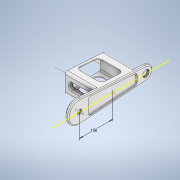
# Autodesk Inventor part: 1.3_1_SideArm
Saved by Autodesk Inventor 2021 (Build 250183000, 183)
## iProperties
Created: 2025-11-12
Part Number: 1.3_1_SideArm
Material: ABS Plastic
Document SubType Name: Modeling
Designer: Admin
Density: 1.06 g/cm^3
Appearance: Smooth - White
Mass: 683.15 g
Surface Area: 1228.56 cm^2
Volume: 644.481 cm^3
Author: Admin
Autodesk Inventor part; units mm, degrees
ref_plane "YZ Plane" through (0, 0, 0) normal (1, 0, 0) x (0, 1, 0)
ref_plane "XZ Plane" through (0, 0, 0) normal (0, 1, 0) x (-1, 0, 0)
ref_plane "XY Plane" through (0, 0, 0) normal (0, 0, 1) x (1, 0, 0)
sketch "Sketch1" plane through (0, 0, 0) normal (1, 0, 0) x (0, 1, 0)
  circle A0 centre (0, 0) radius 50
  circle A1 centre (0, -300) radius 30
  line L0 (0, 0) -> (0, -300) construction
  line L1 (49.8888, -3.3333) -> (29.9333, -302)
  line L2 (-49.8888, -3.3333) -> (-29.9333, -302)
  dimension "d0" = 300
  dimension "d1" = 100
  dimension "d2" = 60
  constraints: 6 end point, 4 point on circle, 3 tangent, 2 centre point, 1 coincident, 1 equal length, 1 vertical
  measures "d0" distance of L0.start L0.end
  measures "d1" diameter of A0
  measures "d2" diameter of A1
extrude "Extrusion1" add sketch "Sketch1" along normal blind 11
sketch "Sketch2" plane through (0, 0, 0) normal (0, 1, 0) x (-1, 0, 0)
  line L0 (0, 0) -> (0, 42.5)
  line L1 (0, 50) -> (0, -3.3333) projected
  line L2 (0, 42.5) -> (1, 42.5)
  line L3 (1, 42.5) -> (1, 40)
  line L4 (1, 40) -> (10, 40)
  line L5 (10, 40) -> (10, 0)
  line L6 (10, 0) -> (0, 0)
  dimension "d7" = 40
  dimension "d8" = 10
  dimension "d9" = 1
  dimension "d99" = 42.5
  constraints: 12 end point, 5 perpendicular, 1 collinear
  measures "d7" distance of L4.end L5.end
  measures "d8" distance between parallel lines of L0 L5
  measures "d9" distance of L0.end L2.end
  measures "d99" distance between parallel lines of L2 L6
revolve "Revolution1" add sketch "Sketch2" angle 360 about axis through (-10, 0, 0) along (1, 0, 0)
sketch "Sketch3" plane through (0, 0, 0) normal (0, 1, 0) x (-1, 0, 0)
  line L0 (10, -40) -> (10, 40) projected
  line L1 (10, -30) -> (-2, -30)
  line L2 (-2, -30) -> (-2, -12)
  line L3 (-2, -12) -> (-5, -12)
  line L4 (-5, -12) -> (-5, -10)
  line L5 (-5, -10) -> (-11, -10)
  line L6 (-11, -10) -> (-11, 0)
  line L7 (-11, 50) -> (-11, -3.3333) projected
  line L8 (-11, 0) -> (10, 0)
  line L9 (10, 0) -> (10, -30)
  line L10 (14.2, 0) -> (-15.2, 0) projected
  point P0 (0, 0)
  point P1 (10, 0)
  dimension "d11" = 30
  dimension "d12" = 12
  dimension "d13" = 6
  dimension "d14" = 3
  dimension "d15" = 12
  dimension "d16" = 10
  constraints: 16 end point, 6 perpendicular, 2 point on line, 1 collinear, 1 horizontal
  measures "d11" distance between parallel lines of L8 L1
  measures "d12" distance of L1.start L1.end
  measures "d13" distance of L4.end L5.end
  measures "d14" distance of L2.end L3.end
  measures "d15" distance between parallel lines of L8 L3
  measures "d16" distance between parallel lines of L8 L5
revolve "Revolution2" cut sketch "Sketch3" angle 360 about axis through (-10, 0, 0) along (1, 0, 0)
sketch "Sketch4" plane through (2, 0, 0) normal (-1, 0, 0) x (0, 0, 1)
  line L0 (-16.2635, -16.2635) -> (16.2635, -16.2635)
  line L1 (16.2635, -16.2635) -> (16.2635, 16.2635)
  line L2 (16.2635, 16.2635) -> (-16.2635, 16.2635)
  line L3 (-16.2635, 16.2635) -> (-16.2635, -16.2635)
  line L4 (-16.2635, -16.2635) -> (16.2635, 16.2635) construction
  line L5 (16.2635, -16.2635) -> (-16.2635, 16.2635) construction
  circle A0 centre (0, 0) radius 23
  dimension "d18" = 46
  constraints: 12 end point, 3 coincident, 2 midpoint, 2 parallel, 2 perpendicular, 1 horizontal, 3 other
hole "Hole1" at (2, 16.2635, 16.2635) at (2, -16.2635, -16.2635) direction (1, 0, 0) diameter 4.5 end through all clearance for "Countersunk Flat Head Screw ISO 2009/7046" size "M4" standard "ISO"
sketch "Sketch5" plane through (0, 0, 0) normal (0, 1, 0) x (-1, 0, 0)
  line L0 (0, -300) -> (-11, -300)
  line L1 (0, -300) -> (-11, -300)
  line L2 (-11, -300) -> (-11, -314)
  line L3 (-11, -314) -> (-7, -314)
  line L4 (-7, -314) -> (-7, -315)
  line L5 (-7, -315) -> (0, -315)
  line L6 (0, -315) -> (0, -300)
  line L7 (-40, 0) -> (163, 0) projected
  line L8 (0, -406) -> (0, 126) projected
  line L9 (-11, -3.3333) -> (-11, -302) projected
  point P0 (0, 0)
  dimension "d26" = 15
  dimension "d27" = 1
  dimension "d28" = 7
  dimension "d100" = 300
  constraints: 14 end point, 5 perpendicular, 3 collinear
  measures "d26" distance between parallel lines of L0 L5
  measures "d27" distance between parallel lines of L5 L3
  measures "d28" distance of L4.end L5.end
  measures "d100" distance between parallel lines of L7 L0
revolve "Revolution3" cut sketch "Sketch5" angle 360 about axis through (0, 0, -300) along (1, 0, 0)
sketch "Sketch7" plane through (11, 0, 0) normal (1, 0, 0) x (0, 0, -1)
  line L0 (406, 0) -> (-126, 0) projected
  point P0 (0, 0)
  point P1 (150, 0)
  dimension "d36" = 150
  constraints: 1 point on line
  measures "d36" distance of point (0, 0) point (150, 0)
sketch "Sketch8" plane through (0, 0, 0) normal (-1, 0, 0) x (0, 0, 1)
  line L0 (0, 70) -> (0, -70) projected
  circle A0 centre (-300, 0) radius 14 projected
  line L1 (-302, 29.9333) -> (-3.3333, 49.8888) projected
  line L2 (-406, 0) -> (126, 0) projected
  line L3 (-302, 29.9333) -> (-3.3333, 49.8888) projected
  line L4 (-80, 44.7663) -> (-80, -44.7663)
  line L5 (-3.3333, -49.8888) -> (-302, -29.9333) projected
  line L6 (-260, 32.7395) -> (-260, -32.7395)
  line L7 (-240, 34.0758) -> (-240, -34.0758)
  line L8 (-100, 43.43) -> (-100, -43.43)
  line L9 (-260, -32.7395) -> (-240, -34.0758)
  line L10 (-260, 32.7395) -> (-240, 34.0758)
  line L11 (-100, 43.43) -> (-80, 44.7663)
  line L12 (-100, -43.43) -> (-80, -44.7663)
  point P0 (0, 0)
  point P1 (-240, 34.0758)
  point P2 (-260, 32.7395)
  point P3 (-100, 43.43)
  dimension "d66" = 40
  dimension "d67" = 80
  dimension "d68" = 20
  dimension "d69" = 20
  constraints: 16 end point, 7 point on line, 4 collinear, 3 vertical, 1 coincident, 1 parallel
  measures "d66" distance from line of point (-300, 0) L6
  measures "d67" distance between parallel lines of L0 L4
  measures "d68" distance between parallel lines of L7 L6
  measures "d69" distance between parallel lines of L4 L8
extrude "Extrusion4" add sketch "Sketch8" along normal blind 134 contours L1 L7 L2 L6 | L2 L7 L5 L6 | L1 L4 L2 L8 | L2 L4 L5 L8
fillet "Fillet3" radius 10 8 edges at (-67, 44.7663, -80) (-67, 43.43, -100) (-67, 34.0758, -240) (-67, 32.7395, -260) (-67, -43.43, -100) (-67, -44.7663, -80) (-67, -34.0758, -240) (-67, -32.7395, -260)
sketch "Sketch10" plane through (11, 0, 0) normal (1, 0, 0) x (0, 0, -1)
  line L0 (40, 37.4166) -> (40, -37.4166)
  line L1 (40, -37.4166) -> (260, -22.7172)
  line L2 (260, -22.7172) -> (260, 22.7172)
  line L3 (260, 22.7172) -> (40, 37.4166)
  line L4 (302, 29.9333) -> (3.3333, 49.8888) projected
  line L5 (3.3333, -49.8888) -> (302, -29.9333) projected
  circle A0 centre (300, 0) radius 14 projected
  point P0 (0, 0)
  dimension "d72" = 40
  dimension "d73" = 40
  dimension "d74" = 10
  dimension "d75" = 10
  constraints: 8 end point, 3 parallel, 1 coincident, 1 vertical
  measures "d72" distance from line of L0 point (0, 0)
  measures "d73" distance from line of L2 point (300, 0)
  measures "d74" distance between parallel lines of L4 L3
  measures "d75" distance between parallel lines of L5 L1
extrude "Extrusion5" cut sketch "Sketch10" against normal blind 5 contours L3 L2 L1 L0
fillet "Fillet4" radius 10 4 edges at (8.5, 37.4166, -40) (8.5, -37.4166, -40) (8.5, 22.7172, -260) (8.5, -22.7172, -260)
chamfer "Chamfer1" distance 4 angle 45 4 edges at (11, 39.911, -152.6667) (11, 0, 50) (11, -39.911, -152.6667) (11, 0, -330)
sketch "Sketch11" plane through (-134, 0, 0) normal (-1, 0, 0) x (0, 0, 1)
  line L0 (-406, 0) -> (126, 0) projected
  line L1 (-90.6667, 44.0536) -> (-250.6667, 33.3631) projected
  line L2 (0, 70) -> (0, -70) projected
  circle A0 centre (-300, 0) radius 14 projected
  point P0 (0, 0)
  point P1 (-250, 17)
  point P2 (-90, 30)
  point P3 (-90, -30)
  point P4 (-250, -17)
  dimension "d82" = 17
  dimension "d83" = 17
  dimension "d84" = 30
  dimension "d85" = 30
  dimension "d93" = 90
  dimension "d94" = 90
  dimension "d95" = 50
  dimension "d96" = 50
  constraints: 1 coincident
  measures "d82" distance from line of L0 point (-250, 17)
  measures "d83" distance from line of L0 point (-250, -17)
  measures "d84" distance from line of L0 point (-90, 30)
  measures "d85" distance from line of L0 point (-90, -30)
  measures "d93" horizontal distance of point (0, 0) point (-90, 30)
  measures "d94" distance from line of L2 point (-90, -30)
  measures "d95" horizontal distance of point (-250, 17) point (-300, 0)
  measures "d96" horizontal distance of point (-300, 0) point (-250, -17)
hole "Hole2" at (-134, 17, -250) at (-134, -17, -250) at (-134, 30, -90) at (-134, -30, -90) direction (1, 0, 0) diameter 8 depth 15 tip angle 118
fillet "Fillet5" radius 0.3 1 edges at (7, 0, -285)
fillet "Fillet6" radius 0.5 1 edges at (-1, 0, -40)
sketch "Sketch12" plane through (0, 0, 0) normal (-1, 0, 0) x (0, 0, 1)
  arc A0 (-240, 23.3854) -> (-250.6667, 33.3631) centre (-250, 23.3854) ccw projected
  arc A1 (-90.6667, 44.0536) -> (-100, 34.0758) centre (-90, 34.0758) ccw projected
  line L0 (-250.6667, 33.3631) -> (-90.6667, 44.0536)
  line L1 (-50.6667, 36.7039) -> (-250.6667, 23.3408) projected
  line L2 (-240, 23.3854) -> (-240, -23.3854) projected
  line L3 (-250.6667, 33.3631) -> (-240, 13.9688)
  line L4 (-240, 13.9688) -> (-240, 30.0669)
  line L5 (-100, 25.3948) -> (-100, 39.421)
  line L6 (-100, 39.421) -> (-240, 30.0669)
  arc A2 (-80, 34.0758) -> (-90.6667, 44.0536) centre (-90, 34.0758) ccw projected
  line L7 (-100, 25.3948) -> (-90.6667, 44.0536)
  line L8 (-100, 34.0758) -> (-100, -34.0758) projected
  point P0 (0, 0)
  dimension "d105" = 4
  constraints: 12 end point, 2 point on line, 1 collinear, 1 parallel, 1 tangent, 1 vertical
  measures "d105" distance between parallel lines of L0 L6
extrude "Extrusion6" add sketch "Sketch12" along normal up to surface (134 mm away) contours L2 L3 L1 A0 | A0 L1 L4 | L1 L3 A0 | A0 L0 A1 L5 L6 L4 L1 | L5 A1 L7 L1 | L1 L7 L5
mirror "Mirror1" about plane through (0, 0, 0) normal (0, 1, 0) of "Extrusion6"
sketch "Sketch13" plane through (0, 0, 0) normal (0, 1, 0) x (-1, 0, 0)
  line L0 (124, -220) -> (10, -220)
  line L1 (10, -220) -> (10, -120)
  line L2 (10, -120) -> (124, -120)
  line L3 (124, -120) -> (124, -220)
  line L4 (0, -240) -> (134, -240) projected
  line L5 (0, -100) -> (134, -100) projected
  line L6 (134, -100) -> (134, -240) projected
  line L7 (0, -240) -> (0, -100) projected
  line L8 (163, -250) -> (-40, -250) projected
  line L9 (-40, -90) -> (163, -90) projected
  point P0 (0, 0)
  dimension "d108" = 10
  dimension "d109" = 10
  dimension "d112" = 30
  dimension "d113" = 30
  constraints: 8 end point, 2 parallel, 1 horizontal, 1 perpendicular
  measures "d108" distance between parallel lines of L6 L3
  measures "d109" distance between parallel lines of L7 L1
  measures "d112" distance between parallel lines of L8 L0
  measures "d113" distance between parallel lines of L9 L2
extrude "Extrusion7" cut sketch "Sketch13" against normal through all both and the other way through all contours L0 L1 L2 L3
fillet "Fillet7" radius 20 8 edges at (-10, 33.4077, -220) (-10, 40.0892, -120) (-124, -33.4077, -220) (-124, 33.4077, -220) (-124, -40.0892, -120) (-124, 40.0892, -120) (-10, -33.4077, -220) (-10, -40.0892, -120)
sketch "Sketch14" plane through (0, -34.0758, -80) normal (0, 0, 1) x (1, 0, 0)
  line L0 (-114, 48.1516) -> (-20, 48.1516)
  line L1 (-20, 48.1516) -> (-20, 20)
  line L2 (-20, 20) -> (-114, 20)
  line L3 (-114, 20) -> (-114, 48.1516)
  line L4 (-134, 0) -> (-134, 68.1516) projected
  line L5 (0, 68.1516) -> (0, 0) projected
  line L6 (-134, 68.1516) -> (0, 68.1516) projected
  line L7 (0, 0) -> (-134, 0) projected
  point P0 (0, 34.0758)
  dimension "d115" = 20
  dimension "d116" = 20
  dimension "d117" = 20
  dimension "d118" = 20
  constraints: 8 end point, 2 parallel, 1 horizontal, 1 perpendicular
  measures "d115" distance between parallel lines of L4 L3
  measures "d116" distance between parallel lines of L5 L1
  measures "d117" distance between parallel lines of L6 L0
  measures "d118" distance between parallel lines of L7 L2
extrude "Extrusion8" cut sketch "Sketch14" against normal blind 40 contours L0 L1 L2 L3
fillet "Fillet8" radius 10 4 edges at (-20, -14.0758, -90) (-114, 14.0758, -90) (-114, -14.0758, -90) (-20, 14.0758, -90)
fillet "Fillet9" radius 5 4 edges at (-67, 39.421, -100) (-67, 30.0669, -240) (-67, -30.0669, -240) (-67, -39.421, -100)
fillet "Fillet10" radius 5 16 edges at (-22.9289, 11.1469, -80) (-20, 0, -80) (-22.9289, -11.1469, -80) (-67, -14.0758, -80) (-111.0711, -11.1469, -80) (-114, 0, -80) (-111.0711, 11.1469, -80) (-67, 14.0758, -80) (-22.9289, -11.1469, -100) (-20, 0, -100) (-22.9289, 11.1469, -100) (-67, 14.0758, -100) (-111.0711, 11.1469, -100) (-114, 0, -100) (-111.0711, -11.1469, -100) (-67, -14.0758, -100)
chamfer "Chamfer2" distance 1 angle 45 3 edges at (11, 0, -286) (0, 0, -285) (-10, 0, -40)
equation "\"d113\" = d112"
equation "\"d116\" = d115"
equation "\"d118\" = d117"
body "Solid1"
